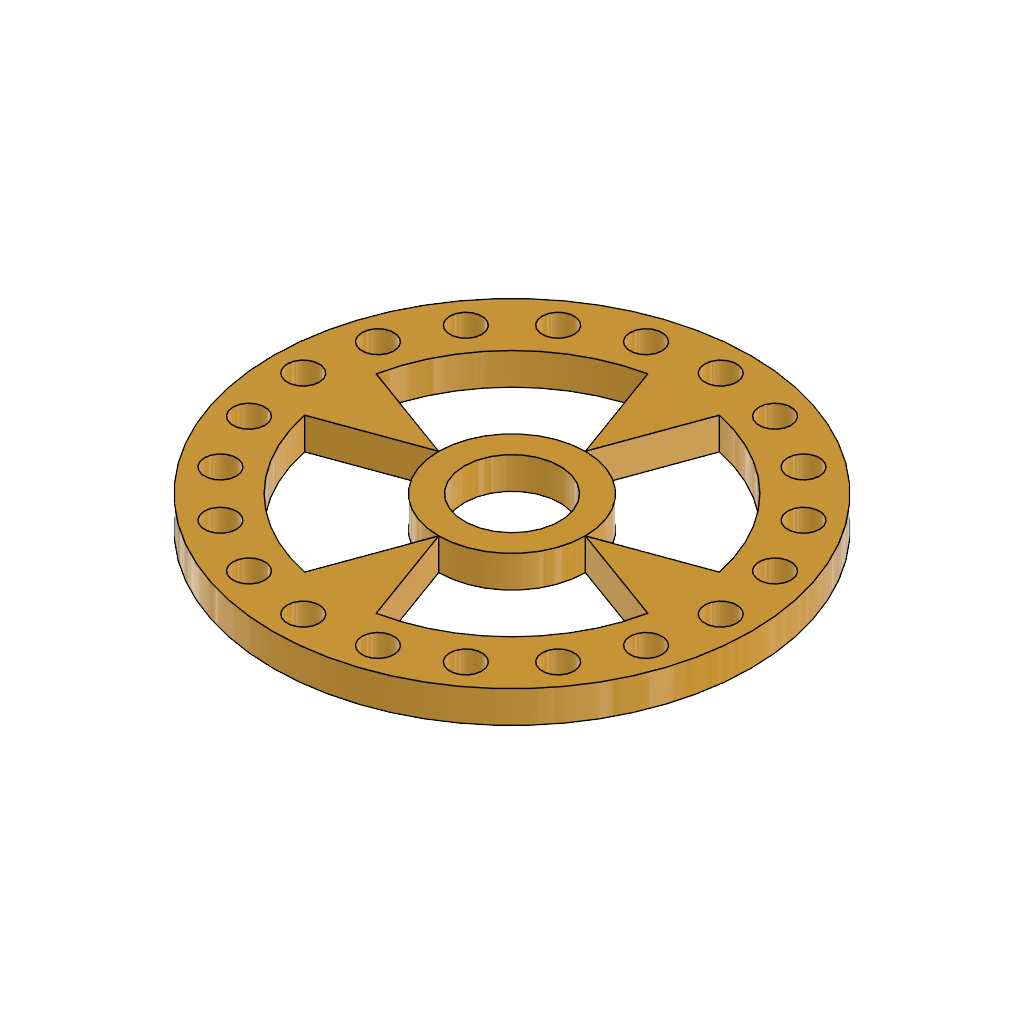
disque_doseur_de_graine (Autodesk Fusion 360 design; units mm, degrees)
part number: 2026-10-27-15-51-09-455
Autodesk Fusion 360 part; units mm, degrees
sketch "Esquisse1" plane through (0, 0, 0) normal (0, 0, 1) x (1, 0, 0)
  circle A0 centre (0, 0) radius 7.5
  circle A1 centre (0, 0) radius 11.5
  circle A2 centre (0, 0) radius 37.5
  line L0 (0, 11.5) -> (-5.6128, 26.9211)
  line L1 (0, 11.5) -> (5.6128, 26.9211)
  line L2 (-11.5, 0) -> (-26.9211, -5.6128)
  line L3 (-11.5, 0) -> (-26.9211, 5.6128)
  line L4 (0, -11.5) -> (5.6128, -26.9211)
  line L5 (0, -11.5) -> (-5.6128, -26.9211)
  line L6 (11.5, 0) -> (26.9211, 5.6128)
  line L7 (11.5, 0) -> (26.9211, -5.6128)
  arc A3 (26.9211, 5.6128) -> (5.6128, 26.9211) centre (0, 0) ccw
  arc A4 (-5.6128, 26.9211) -> (-26.9211, 5.6128) centre (0, 0) ccw
  arc A5 (-26.9211, -5.6128) -> (-5.6128, -26.9211) centre (0, 0) ccw
  arc A6 (5.6128, -26.9211) -> (26.9211, -5.6128) centre (0, 0) ccw
  line L8 (0, 37.5) -> (0, 28) construction
  circle A7 centre (0, 32.75) radius 2.5
  circle A8 centre (-10.1203, 31.1471) radius 2.5
  circle A9 centre (-19.25, 26.4953) radius 2.5
  circle A10 centre (-26.4953, 19.25) radius 2.5
  circle A11 centre (-31.1471, 10.1203) radius 2.5
  circle A12 centre (-32.75, 0) radius 2.5
  circle A13 centre (-31.1471, -10.1203) radius 2.5
  circle A14 centre (-26.4953, -19.25) radius 2.5
  circle A15 centre (-19.25, -26.4953) radius 2.5
  circle A16 centre (-10.1203, -31.1471) radius 2.5
  circle A17 centre (0, -32.75) radius 2.5
  circle A18 centre (10.1203, -31.1471) radius 2.5
  circle A19 centre (19.25, -26.4953) radius 2.5
  circle A20 centre (26.4953, -19.25) radius 2.5
  circle A21 centre (31.1471, -10.1203) radius 2.5
  circle A22 centre (32.75, 0) radius 2.5
  circle A23 centre (31.1471, 10.1203) radius 2.5
  circle A24 centre (26.4953, 19.25) radius 2.5
  circle A25 centre (19.25, 26.4953) radius 2.5
  circle A26 centre (10.1203, 31.1471) radius 2.5
  dimension "d1" = 4
  dimension "d2" = 15
  dimension "d4" = 30
  dimension "d6" = 140
  dimension "d8" = 360
  dimension "d9" = 5
  dimension "d11" = 360
  constraint coincident A0.centre A1.centre
  constraint coincident A1 L0.start
  constraint concentric A0 A3
  constraint concentric A3 A4
  constraint concentric A4 A5
  constraint concentric A5 A6
  constraint coincident A2 L8.start
  constraint perpendicular A2 L8
  constraint midpoint L8 A7.centre
  measures "d2" diameter of A0
  measures "d6" angle of L0 L1
  measures "d9" diameter of A7
extrude "Extrusion1" add sketch "Esquisse1" along normal blind 5 contours A1 | A2
